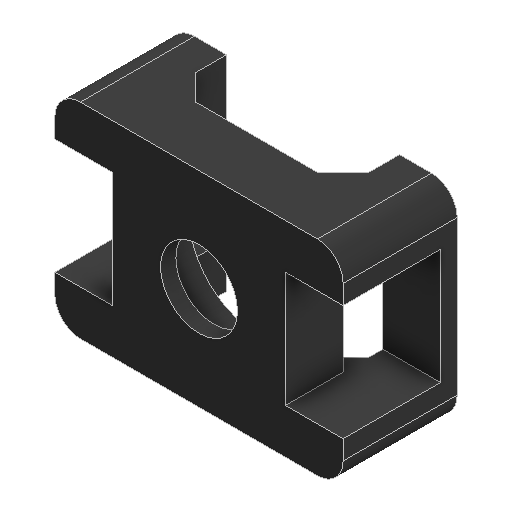
# Autodesk Inventor part: COTS_Profihot_HC-2-22x16_Zip_Tie_Anchor
Saved by Autodesk Inventor 2027 (Build 310192060, 192F)
## iProperties
Created: 2025-10-04
Part Number: COTS_Profihot_HC-2-22x16_Zip_Tie_Anchor
Material: Generic
Document SubType Name: Modeling
Designer: Andrzej
Density: 1 g/cm^3
Appearance: Rubber - Black
Author: Andrzej
Autodesk Inventor part; units mm, degrees
ref_plane "YZ Plane" through (0, 0, 0) normal (1, 0, 0) x (0, 1, 0)
ref_plane "XZ Plane" through (0, 0, 0) normal (0, 1, 0) x (-1, 0, 0)
ref_plane "XY Plane" through (0, 0, 0) normal (0, 0, 1) x (1, 0, 0)
sketch "Sketch1" plane through (0, 0, 0) normal (0, 0, 1) x (1, 0, 0)
  line L0 (-11.25, 8) -> (11.25, 8)
  line L1 (11.25, 8) -> (11.25, -8)
  line L2 (11.25, -8) -> (-11.25, -8)
  line L3 (-11.25, -8) -> (-11.25, 8)
  line L4 (11.25, 4.5) -> (6.75, 4.5)
  line L5 (6.75, 4.5) -> (6.75, -4.5)
  line L6 (6.75, -4.5) -> (11.25, -4.5)
  line L7 (0, 0) -> (0, 15.1576)
  line L8 (-11.25, 4.5) -> (-6.75, 4.5)
  line L9 (-6.75, 4.5) -> (-6.75, -4.5)
  line L10 (-6.75, -4.5) -> (-11.25, -4.5)
  line L11 (6.75, 4.5) -> (6.75, 8)
  line L12 (6.75, -4.5) -> (6.75, -8)
  line L13 (-6.75, -4.5) -> (-6.75, -8)
  line L14 (-6.75, 4.5) -> (-6.75, 8)
  circle A0 centre (0, 0) radius 3
  circle A1 centre (0, 0) radius 5.25
  dimension "d0" = 22.5
  dimension "d1" = 16
  dimension "d2" = 8
  dimension "d3" = 11.25
  dimension "d4" = 9
  dimension "d5" = 4.5
  dimension "d6" = 3.5
  dimension "d7" = 6
  dimension "d8" = 10.5
  constraints: 30 end point, 8 point on line, 5 perpendicular, 4 symmetric about line, 2 centre point, 2 coincident, 2 horizontal, 2 parallel, 1 vertical
  measures "d0" distance of L0.start L0.end
  measures "d1" distance of L2.end L0.start
  measures "d2" distance from line of L0 L7.start
  measures "d3" distance from line of L3 L7.start
  measures "d4" distance between parallel lines of L6 L4
  measures "d5" distance between parallel lines of L1 L5
  measures "d6" distance between parallel lines of L2 L6
  measures "d7" diameter of A0
  measures "d8" diameter of A1
extrude "Extrusion1" add sketch "Sketch1" along normal blind 4.5 contours L0 L14 L8 L3 | L0 L11 L5 L12 L2 L13 L9 L14 | L10 L13 L2 L3 | L0 L1 L4 L11 | L6 L1 L2 L12 | A1
extrude "Extrusion2" cut sketch "Sketch1" along normal blind 3.3 contours A1
extrude "Extrusion3" add sketch "Sketch1" against normal blind 4.4 contours L0 L14 L8 L3 | L10 L13 L2 L3 | L0 L1 L4 L11 | L6 L1 L2 L12
sketch "Sketch2" plane through (0, 0, -4.4) normal (0, 0, -1) x (-1, 0, 0)
  line L0 (11.25, -4.5) -> (6.75, -4.5) projected
  line L1 (6.75, -4.5) -> (6.75, -8) projected
  line L2 (6.75, -8) -> (11.25, -8) projected
  line L3 (11.25, -8) -> (11.25, -4.5) projected
  line L4 (11.25, 8) -> (6.75, 8) projected
  line L5 (6.75, 8) -> (6.75, 4.5) projected
  line L6 (6.75, 4.5) -> (11.25, 4.5) projected
  line L7 (11.25, 4.5) -> (11.25, 8) projected
  line L8 (-11.25, 4.5) -> (-6.75, 4.5) projected
  line L9 (-6.75, 4.5) -> (-6.75, 8) projected
  line L10 (-6.75, 8) -> (-11.25, 8) projected
  line L11 (-11.25, 8) -> (-11.25, 4.5) projected
  line L12 (-11.25, -8) -> (-6.75, -8) projected
  line L13 (-6.75, -8) -> (-6.75, -4.5) projected
  line L14 (-6.75, -4.5) -> (-11.25, -4.5) projected
  line L15 (-11.25, -4.5) -> (-11.25, -8) projected
  line L16 (11.25, -4.5) -> (11.25, 4.5)
  line L17 (6.75, 4.5) -> (6.75, -4.5)
  line L18 (-6.75, -4.5) -> (-6.75, 4.5)
  line L19 (-11.25, 4.5) -> (-11.25, -4.5)
  point P0 (0, 0)
  constraints: 8 end point, 2 collinear, 1 parallel, 1 perpendicular
extrude "Extrusion4" add sketch "Sketch2" against normal blind 1.3 contours L0 L17 L6 L16 | L8 L18 L14 L19
fillet "Fillet1" radius 2 4 edges at (11.25, 8, 0.05) (-11.25, 8, 0.05) (11.25, -8, 0.05) (-11.25, -8, 0.05)
chamfer "Chamfer1" distance 2 angle 45 4 edges at (-6.75, -6.25, 0) (-6.75, 6.25, 0) (6.75, 6.25, 0) (6.75, -6.25, 0)
equation "\"d2\" = 0.5 * d1"
equation "\"d3\" = 0.5 * d0"
equation "\"d6\" = -0.5 * d4 + 0.5 * d1"
body "Solid1"
